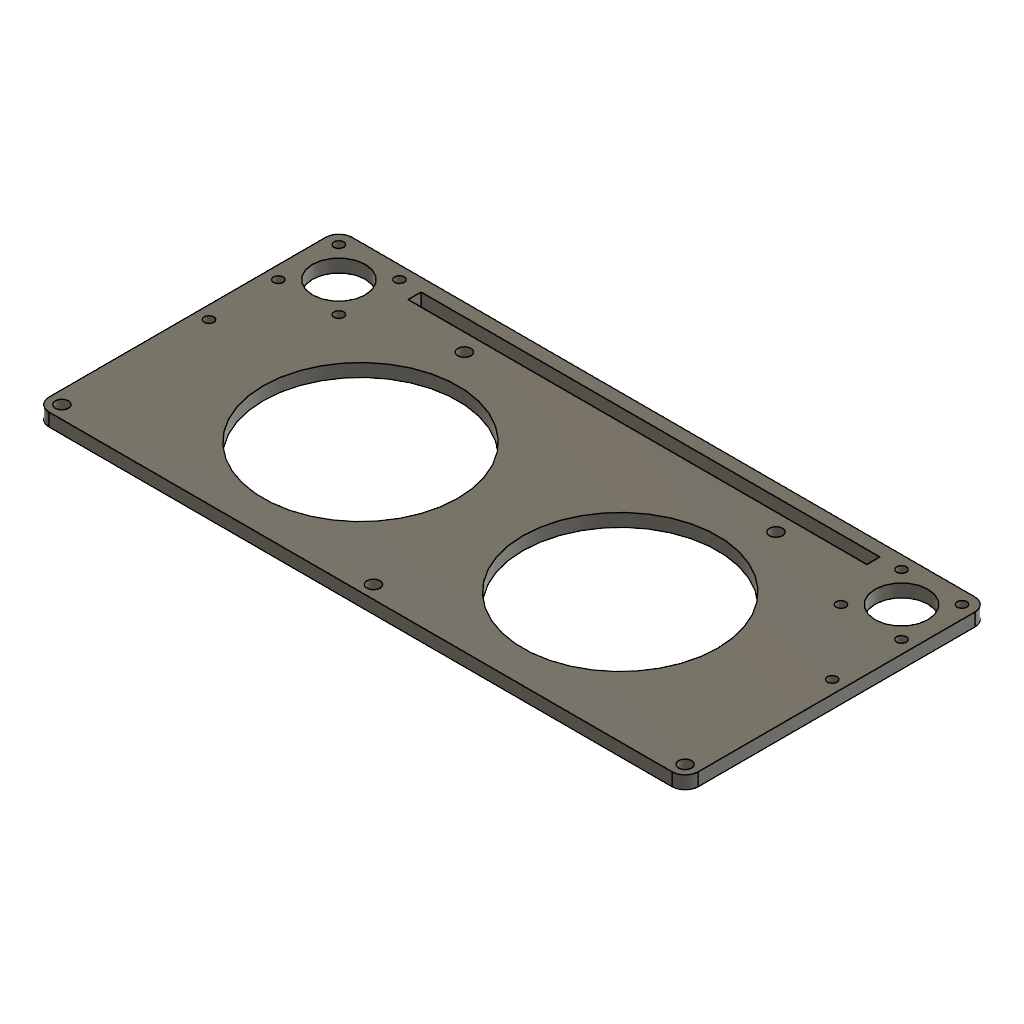
02-17_측판_오른쪽 (Autodesk Fusion 360 design; units mm, degrees)
Autodesk Fusion 360 part; units mm, degrees
sketch "스케치1" plane through (0, 0, 0) normal (0, 1, 0) x (1, 0, 0)
  line L0 (-72, 35) -> (72, 35)
  line L1 (75, 32) -> (75, -32)
  line L2 (72, -35) -> (-72, -35)
  line L3 (-75, -32) -> (-75, 32)
  line L4 (0, 35) -> (0, -35) construction
  arc A0 (-72, 35) -> (-75, 32) centre (-72, 32) ccw
  arc A1 (75, 32) -> (72, 35) centre (72, 32) ccw
  arc A2 (72, -35) -> (75, -32) centre (72, -32) ccw
  arc A3 (-75, -32) -> (-72, -35) centre (-72, -32) ccw
  circle A4 centre (-30, -5) radius 22.5
  circle A5 centre (30, -5) radius 22.5
  circle A6 centre (-65, 25) radius 6.1
  circle A7 centre (65, 25) radius 6.1
  line L5 (-53, 32) -> (53, 32)
  line L6 (53, 32) -> (53, 29)
  line L7 (53, 29) -> (-53, 29)
  line L8 (-53, 29) -> (-53, 32)
  point P0 (-75, 35)
  point P1 (75, 35)
  point P2 (75, -35)
  dimension "d1" = 150
  dimension "d2" = 70
  dimension "d3" = 3
  dimension "d4" = 45
  dimension "d5" = 45
  dimension "d6" = 5
  dimension "d7" = 5
  dimension "d8" = 30
  dimension "d9" = 60
  dimension "d10" = 12.2
  dimension "d11" = 12.2
  dimension "d12" = 25
  dimension "d13" = 25
  dimension "d14" = 130
  dimension "d15" = 10
  dimension "d16" = 106
  dimension "d17" = 3
  dimension "d18" = 3
  dimension "d19" = 22
  dimension "d20" = 75
  constraint horizontal L0
  constraint vertical L1
  constraint horizontal L2
  constraint vertical L3
  constraint midpoint origin L4
  constraint coincident L0 L4.start
  constraint coincident P0 L3
  constraint coincident P0 L0
  constraint tangent L3 A0
  constraint tangent L0 A0
  constraint coincident P1 L0
  constraint coincident P1 L1
  constraint tangent L0 A1
  constraint tangent L1 A1
  constraint equal A0 A1
  constraint coincident L2 L4.end
  constraint coincident P2 L1
  constraint coincident P2 L2
  constraint tangent L1 A2
  constraint tangent L2 A2
  constraint equal A0 A2
  constraint tangent L2 A3
  constraint tangent L3 A3
  constraint equal A0 A3
  constraint horizontal L5
  constraint vertical L6
  constraint horizontal L7
  constraint vertical L8
  measures "d1" distance of P0 P1
  measures "d2" distance of P1 P2
  measures "d3" radius of A0
  measures "d4" diameter of A4
  measures "d5" diameter of A5
  measures "d6" vertical distance of origin A4.centre
  measures "d7" vertical distance of origin A5.centre
  measures "d8" horizontal distance of origin A4.centre
  measures "d9" distance of A4.centre A5.centre
  measures "d10" diameter of A6
  measures "d11" diameter of A7
  measures "d12" vertical distance of origin A7.centre
  measures "d13" vertical distance of origin A6.centre
  measures "d14" distance of A6.centre A7.centre
  measures "d15" distance of L1 A7.centre
  measures "d16" distance of L6.end L7.end
  measures "d17" distance of L0 L5
  measures "d18" distance of L5.end L6.end
  measures "d19" distance of L3 L8
  measures "d20" distance of origin L3
extrude "돌출1" add sketch "스케치1" along normal blind 3
sketch "스케치2" plane through (0, 3, 0) normal (0, 1, 0) x (-1, 0, 0)
  circle A0 centre (-30, 5) radius 22.5
  line L0 (-53, -29) -> (53, -29)
  line L1 (53, -29) -> (53, -32)
  line L2 (53, -32) -> (-53, -32)
  line L3 (-53, -32) -> (-53, -29)
  circle A1 centre (30, 5) radius 22.5
  circle A2 centre (65, -25) radius 6.1
  circle A3 centre (-65, -25) radius 6.1
  arc A4 (72, -35) -> (75, -32) centre (72, -32) ccw
  line L4 (75, -32) -> (75, 32)
  arc A5 (75, 32) -> (72, 35) centre (72, 32) ccw
  line L5 (72, 35) -> (-72, 35)
  arc A6 (-72, 35) -> (-75, 32) centre (-72, 32) ccw
  line L6 (-75, 32) -> (-75, -32)
  arc A7 (-75, -32) -> (-72, -35) centre (-72, -32) ccw
  line L7 (-72, -35) -> (72, -35)
  circle A8 centre (36, -25) radius 1.5
  circle A9 centre (-36, -25) radius 1.5
  circle A10 centre (-72, 32) radius 1.5
  circle A11 centre (0, 32) radius 1.5
  circle A12 centre (72, 32) radius 1.5
  dimension "d23" = 3
  dimension "d24" = 3
  dimension "d25" = 3
  dimension "d26" = 3
  dimension "d27" = 3
  dimension "d28" = 72
  dimension "d29" = 25
  dimension "d30" = 25
  dimension "d31" = 39
  constraint concentric A6 A10
  constraint concentric A5 A12
  measures "d23" diameter of A8
  measures "d24" diameter of A9
  measures "d25" diameter of A10
  measures "d26" diameter of A11
  measures "d27" diameter of A12
  measures "d28" horizontal distance of A8.centre A9.centre
  measures "d29" vertical distance of origin A9.centre
  measures "d30" vertical distance of origin A8.centre
  measures "d31" distance of L4 A8.centre
extrude "돌출2" cut sketch "스케치2" against normal blind 3 contours A8 | A9 | A10 | A11 | A12
sketch "스케치3" plane through (0, 3, 0) normal (0, 1, 0) x (-1, 0, 0)
  arc A0 (72, -35) -> (75, -32) centre (72, -32) ccw
  line L0 (75, -32) -> (75, 32)
  arc A1 (75, 32) -> (72, 35) centre (72, 32) ccw
  line L1 (72, 35) -> (-72, 35)
  arc A2 (-72, 35) -> (-75, 32) centre (-72, 32) ccw
  line L2 (-75, 32) -> (-75, -32)
  arc A3 (-75, -32) -> (-72, -35) centre (-72, -32) ccw
  line L3 (-72, -35) -> (72, -35)
  circle A4 centre (-65, -25) radius 6.1
  circle A5 centre (65, -25) radius 6.1
  circle A6 centre (30, 5) radius 22.5
  line L4 (-53, -29) -> (53, -29)
  line L5 (53, -29) -> (53, -32)
  line L6 (53, -32) -> (-53, -32)
  line L7 (-53, -32) -> (-53, -29)
  circle A7 centre (-30, 5) radius 22.5
  circle A8 centre (72, 32) radius 1.5
  circle A9 centre (36, -25) radius 1.5
  circle A10 centre (0, 32) radius 1.5
  circle A11 centre (-36, -25) radius 1.5
  circle A12 centre (-72, 32) radius 1.5
  circle A13 centre (72, -32) radius 1.1
  circle A14 centre (72, -18) radius 1.1
  circle A15 centre (58, -18) radius 1.1
  circle A16 centre (58, -32) radius 1.1
  line L8 (0, -35) -> (0, 35) construction
  circle A17 centre (72, -2) radius 1.1
  circle A18 centre (-58, -32) radius 1.1
  circle A19 centre (-72, -32) radius 1.1
  circle A20 centre (-58, -18) radius 1.1
  circle A21 centre (-72, -18) radius 1.1
  circle A22 centre (-72, -2) radius 1.1
  dimension "d34" = 2.2
  dimension "d35" = 7
  dimension "d36" = 7
  dimension "d38" = 360
  dimension "d39" = 2.2
  dimension "d40" = 16
  dimension "d41" = 3
  constraint midpoint L3 L8.start
  constraint midpoint L1 L8.end
  constraint symmetric A13 L8 A19
  constraint symmetric A14 L8 A21
  constraint symmetric A15 L8 A20
  constraint symmetric A16 L8 A18
  constraint symmetric L8 A17 A22
  measures "d34" diameter of A13
  measures "d35" horizontal distance of A5.centre A0.centre
  measures "d36" vertical distance of A5.centre A0.centre
  measures "d39" diameter of A17
  measures "d40" vertical distance of A14.centre A17.centre
  measures "d41" distance of L0 A17.centre
extrude "돌출3" cut sketch "스케치3" against normal blind 3 contours A13 | A14 | A15 | A16 | A17 | A18 | A19 | A20 | A21 | A22
equation "d20 = d1 / 2"
